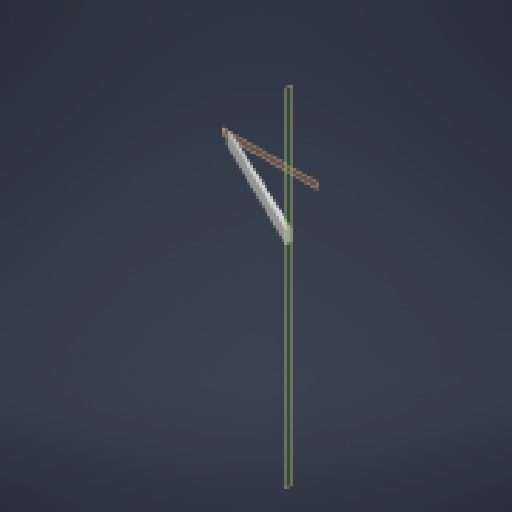
# Autodesk Inventor part: Lower Jaw Diagonals
Saved by Autodesk Inventor 2027 (Build 310192000, 192)
## iProperties
Created: 2026-10-18
Part Number: Lower Jaw Diagonals
Material: Generic
Document SubType Name: Modeling
Designer: lucas
Density: 1 g/cm^3
Appearance: Default
Author: lucas
Autodesk Inventor part; units mm, degrees
ref_plane "YZ Plane" through (0, 0, 0) normal (1, 0, 0) x (0, 1, 0)
ref_plane "XZ Plane" through (0, 0, 0) normal (0, 1, 0) x (-1, 0, 0)
ref_plane "XY Plane" through (0, 0, 0) normal (0, 0, 1) x (1, 0, 0)
ref_plane "Work Plane1" through (0, 0, 0) normal (0, 0, 1) x (1, 0, 0)
sketch "Sketch1" plane through (0, 0, 0) normal (0, 0, 1) x (1, 0, 0)
  line L0 (0, 38.1) -> (38.1, 38.1)
  line L1 (38.1, 38.1) -> (38.1, -50.8)
  line L2 (38.1, -50.8) -> (0, -50.8)
  line L3 (0, -50.8) -> (0, 38.1)
  point P0 (0, 0)
  dimension "d0" = 38.1
  dimension "d1" = 88.9
  constraints: 8 end point, 2 parallel, 1 horizontal, 1 perpendicular, 1 other
  measures "d0" distance of L0.start L0.end
  measures "d1" distance of L2.end L0.start
ref_plane "Work Plane2" through (609.6, -1651, 190.5) normal (-1, 0, 0) x (0, 1, 0)
sketch "Sketch2" plane through (609.6, -1651, 190.5) normal (-1, 0, 0) x (0, 1, 0)
  line L0 (1600.2, 1028.7) -> (1600.2, 38.1) projected
  line L1 (635, 38.1) -> (635, 1028.7) projected
  line L2 (0, 38.1) -> (2235.2, 38.1) projected
  line L3 (1473.2, 38.1) -> (1384.3, 38.1)
  line L4 (1384.3, 38.1) -> (1384.3, 0)
  line L5 (1384.3, 0) -> (1473.2, 0)
  line L6 (1473.2, 0) -> (1473.2, 38.1)
  point P0 (1651, 190.5)
  dimension "d2" = 965.2
  dimension "d3" = 127
  dimension "d4" = 38.1
  dimension "d5" = 88.9
  constraints: 8 end point, 2 parallel, 1 horizontal, 1 perpendicular, 1 point on line
  measures "d2" distance between parallel lines of L1 L0
  measures "d3" distance from line of L0 L3.start
  measures "d4" distance of L3.end L4.end
  measures "d5" distance between parallel lines of L6 L4
loft "Loft1" add profiles "Sketch2", "Sketch1"
body "Solid1"
